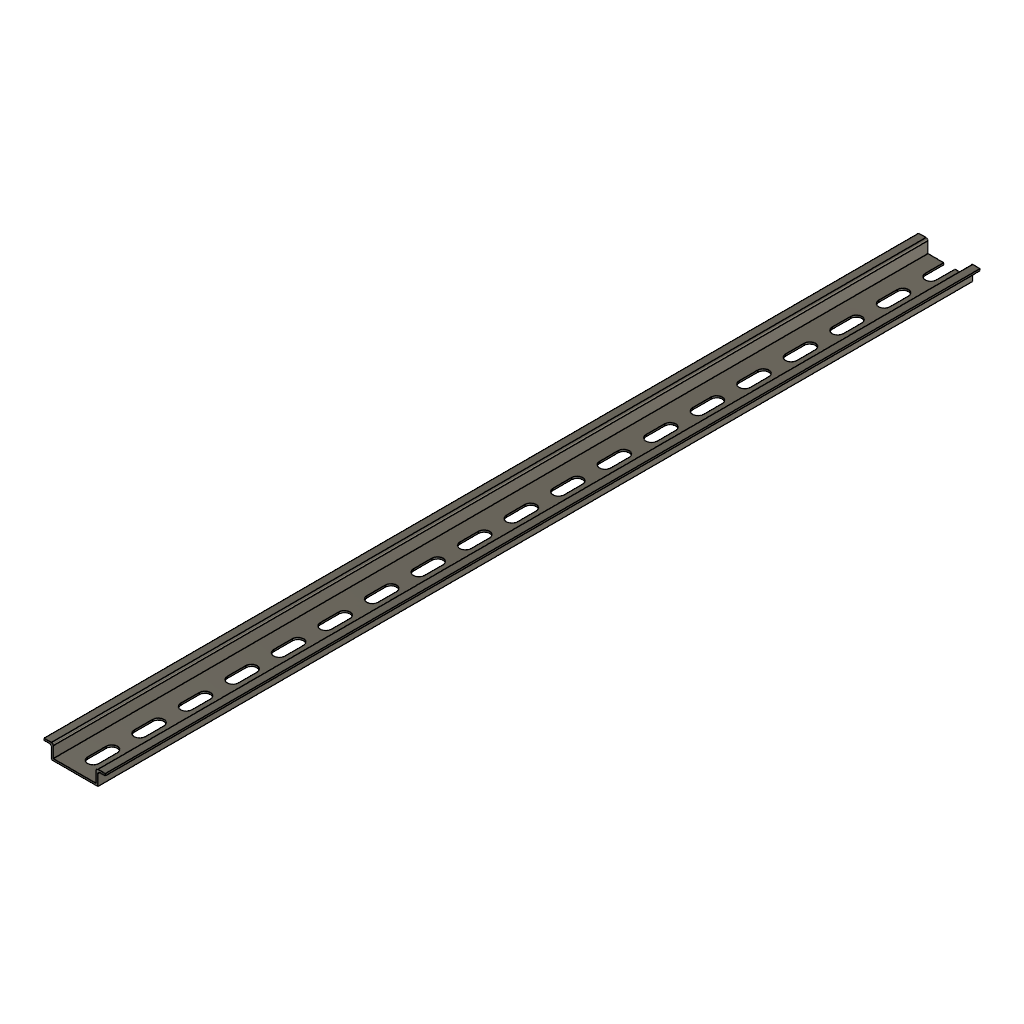
00-16 Mounting rail Placeholder (Autodesk Fusion 360 design; units mm, degrees)
part number: 2026-11-09-08-00-27-953
Autodesk Fusion 360 part; units mm, degrees
sketch "Sketch2" plane through (0, 0, 0) normal (0, 1, 0) x (1, 0, 0)
  line L0 (0, 0) -> (25, 0)
  line L1 (25, 0) -> (25, -1)
  line L2 (25, -1) -> (0, -1)
  line L3 (0, -1) -> (0, 0)
  line L4 (25, -1) -> (24, -1)
  line L5 (24, -1) -> (24, -7)
  line L6 (24, -7) -> (25, -7)
  line L7 (25, -7) -> (25, -1)
  line L8 (0, -1) -> (1, -1)
  line L9 (1, -1) -> (1, -7)
  line L10 (1, -7) -> (0, -7)
  line L11 (0, -7) -> (0, -1)
  line L12 (24, -7) -> (29, -7)
  line L13 (29, -7) -> (29, -8)
  line L14 (29, -8) -> (24, -8)
  line L15 (24, -8) -> (24, -7)
  line L16 (1, -7) -> (-4, -7)
  line L17 (-4, -7) -> (-4, -8)
  line L18 (-4, -8) -> (1, -8)
  line L19 (1, -8) -> (1, -7)
  dimension "d1" = 25
  dimension "d2" = 1
  dimension "d3" = 1
  dimension "d4" = 1
  dimension "d5" = 6
  dimension "d6" = 6
  dimension "d7" = 5
  dimension "d8" = 1
  dimension "d9" = 5
  dimension "d10" = 1
  constraint horizontal L0
  constraint vertical L1
  constraint horizontal L2
  constraint vertical L3
  constraint coincident L0.start L3.end
  constraint horizontal L4
  constraint vertical L5
  constraint horizontal L6
  constraint vertical L7
  constraint horizontal L8
  constraint vertical L9
  constraint horizontal L10
  constraint vertical L11
  constraint horizontal L12
  constraint vertical L13
  constraint horizontal L14
  constraint vertical L15
  constraint horizontal L16
  constraint vertical L17
  constraint horizontal L18
  constraint vertical L19
  measures "d1" distance of L0.start L0.end
  measures "d2" distance of L0.end L1.end
  measures "d3" distance of L5.end L6.end
  measures "d4" distance of L9.end L10.end
  measures "d5" distance of L8.end L9.end
  measures "d6" distance of L1.end L6.end
  measures "d7" distance of L13.end L14.end
  measures "d8" distance of L12.end L13.end
  measures "d9" distance of L17.end L18.end
  measures "d10" distance of L16.end L17.end
extrude "Extrude1" add sketch "Sketch2" along normal blind 470
fillet "Fillet1" radius 1 4 edges at (25, 235, 7) (24, 235, 8) (1, 235, 8) (0, 235, 7)
sketch "Sketch3" plane through (0, 0, 1) normal (0, 0, 1) x (-1, 0, 0)
  line L0 (-1, 0) -> (-24, 0)
  line L1 (-24, 0) -> (-24, -470)
  line L2 (-24, -470) -> (-1, -470)
  line L3 (-1, -470) -> (-1, 0)
  line L4 (-9.5, -10) -> (-15.5, -10)
  line L5 (-15.5, -10) -> (-15.5, -20)
  line L6 (-15.5, -20) -> (-9.5, -20)
  line L7 (-9.5, -20) -> (-9.5, -10)
  arc A0 (-9.5, -10) -> (-15.5, -10) centre (-12.5, -10) ccw
  arc A1 (-15.5, -20) -> (-9.5, -20) centre (-12.5, -20) ccw
  dimension "d15" = 6
  dimension "d16" = 10
  dimension "d17" = 8.5
  dimension "d18" = 10
  constraint horizontal L4
  constraint vertical L5
  constraint horizontal L6
  constraint vertical L7
  constraint tangent L5 A0
  constraint tangent L5 A1
  measures "d15" distance of L4.start L4.end
  measures "d16" distance of L4.end L5.end
  measures "d17" distance of L1 L5
  measures "d18" distance of L0 L4
extrude "Extrude2" cut sketch "Sketch3" against normal blind 15 contours L4 L5 L6 L7 | L4 A0 | L6 A1
pattern_linear "R-Pattern1" count 19 spacing 25 along (0, 1, 0) of "Extrude2"
